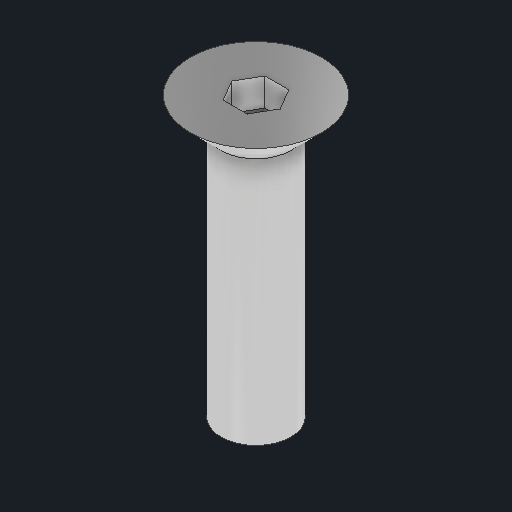
# Autodesk Inventor part: screw_M2.5x10_csk
Saved by Autodesk Inventor 2027.1 (Build 311270010, 270A)
## iProperties
Created: 2026-11-09
Part Number: screw_M2.5x10_csk
Material: Generic
Description: Countersunk screw M2.5x10 (90 deg, ISO 7046 / ISO 10642 style)
Document SubType Name: Modeling
Designer: alexg
Density: 1 g/cm^3
Appearance: Chrome - Polished
Author: alexg
Autodesk Inventor part; units mm, degrees
ref_plane "YZ Plane" through (0, 0, 0) normal (1, 0, 0) x (0, 1, 0)
ref_plane "XZ Plane" through (0, 0, 0) normal (0, 1, 0) x (-1, 0, 0)
ref_plane "XY Plane" through (0, 0, 0) normal (0, 0, 1) x (1, 0, 0)
sketch "Body sketch" plane through (0, 0, 0) normal (0, 0, 1) x (1, 0, 0)
  line L0 (0, 0) -> (0, -10)
  line L1 (0, -10) -> (1.25, -10)
  line L2 (1.25, -10) -> (1.25, -1.1)
  line L3 (1.25, -1.1) -> (2.35, 0)
  line L4 (2.35, 0) -> (0, 0)
  constraints: 10 end point
revolve "Body" add sketch "Body sketch" angle 360 about axis through (0, 0, 0) along (0, -1, 0)
sketch "Hex socket 1.5 sketch" plane through (0, 0, 0) normal (0, 1, 0) x (-1, 0, 0)
  line L0 (-0.866, 0) -> (-0.433, 0.75)
  line L1 (-0.433, 0.75) -> (0.433, 0.75)
  line L2 (0.433, 0.75) -> (0.866, 0)
  line L3 (0.866, 0) -> (0.433, -0.75)
  line L4 (0.433, -0.75) -> (-0.433, -0.75)
  line L5 (-0.433, -0.75) -> (-0.866, 0)
  constraints: 12 end point
extrude "Hex socket 1.5" cut sketch "Hex socket 1.5 sketch" against normal blind 1
body "Solid1"
